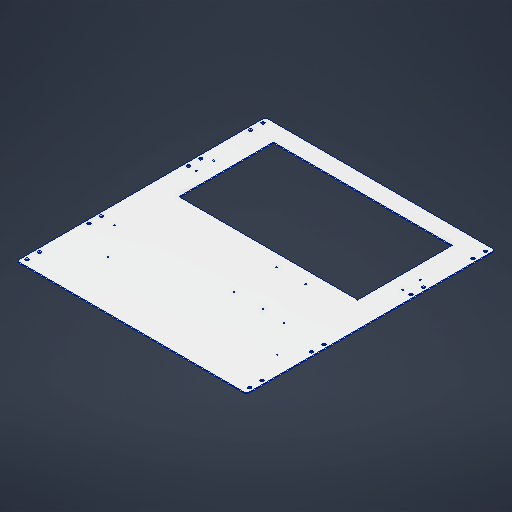
# Autodesk Inventor part: Base Plate
Saved by Autodesk Inventor 2026.2 (Build 302298010, 298A)
## iProperties
Created: 2026-03-19
Part Number: Base Plate
Material: Aluminum 6061
Document SubType Name: Sheet Metal
Designer: User
Density: 2.7 g/cm^3
Sheet Metal Rule: Default_mm
Appearance: Aluminum - Flat
Author: User
Autodesk Inventor part; units mm, degrees
ref_plane "YZ Plane" through (0, 0, 0) normal (1, 0, 0) x (0, 1, 0)
ref_plane "XZ Plane" through (0, 0, 0) normal (0, 1, 0) x (-1, 0, 0)
ref_plane "XY Plane" through (0, 0, 0) normal (0, 0, 1) x (1, 0, 0)
sketch "Sketch1" plane through (0, 0, 0) normal (0, 1, 0) x (-1, 0, 0)
  line L0 (-231.25, -250) -> (231.25, -250)
  line L1 (231.25, -250) -> (231.25, 250)
  line L2 (231.25, 250) -> (-231.25, 250)
  line L3 (-231.25, 250) -> (-231.25, -250)
  line L4 (-231.25, -250) -> (231.25, 250) construction
  line L5 (231.25, -250) -> (-231.25, 250) construction
  point P0 (0, 0)
  point P1 (0, 0)
  constraints: 12 end point, 2 midpoint, 2 parallel, 1 coincident, 1 horizontal, 1 perpendicular
extrude "Plate1" add sketch "Sketch1" along normal blind 2
sketch "Sketch5" plane through (0, 2, 0) normal (0, 1, 0) x (1, 0, 0)
  line L0 (-231.25, -250) -> (231.25, -250) projected
  line L1 (231.25, -250) -> (215, -250)
  line L2 (-231.25, 250) -> (-231.25, -250) projected
  line L3 (231.25, -250) -> (231.25, 250) projected
  line L4 (231.25, -225) -> (238.202, -225) construction
  line L5 (223.932, -237) -> (223.932, -250)
  line L6 (223.932, -237) -> (223.932, -212)
  line L7 (223.932, -212) -> (223.932, -187)
  line L8 (223.932, -187) -> (223.932, -162)
  line L9 (223.932, -237) -> (231.25, -237)
  line L10 (223.932, -162) -> (223.932, -137)
  line L11 (223.932, -137) -> (223.932, -112)
  line L12 (223.932, -112) -> (223.932, -87)
  line L13 (223.932, -87) -> (223.932, -62)
  line L14 (223.932, -62) -> (223.932, -37)
  line L15 (223.932, 13) -> (223.932, 38)
  line L16 (223.932, 38) -> (223.932, 63)
  line L17 (223.932, 63) -> (223.932, 88)
  line L18 (223.932, 88) -> (223.932, 113)
  line L19 (223.932, 113) -> (223.932, 138)
  line L20 (223.932, 138) -> (223.932, 163)
  line L21 (223.932, 163) -> (223.932, 188)
  line L22 (223.932, 188) -> (223.932, 213)
  line L23 (223.932, 213) -> (223.932, 238)
  line L24 (223.932, 238) -> (223.932, 250)
  line L25 (231.25, 250) -> (-231.25, 250) projected
  line L26 (223.932, -37) -> (223.932, -12)
  line L27 (223.932, -12) -> (223.932, 13)
  line L28 (-231.25, -250) -> (-223.932, -250)
  line L29 (-223.932, -250) -> (-223.932, -237)
  line L30 (-223.932, -237) -> (-223.932, -212)
  line L31 (-223.932, -212) -> (-223.932, -112)
  line L32 (-223.932, -112) -> (-223.932, -87)
  line L33 (-223.932, -87) -> (-223.932, 88)
  line L34 (-223.932, 88) -> (-223.932, 113)
  line L35 (-223.932, 113) -> (-223.932, 213)
  line L36 (-223.932, 213) -> (-223.932, 238)
  line L37 (-223.932, 238) -> (-223.932, 250)
  point P0 (0, 0)
  dimension "d126" = 13
  dimension "d127" = 25
  dimension "d128" = 25
  dimension "d129" = 25
  dimension "d130" = 7.318
  dimension "d131" = 25
  dimension "d132" = 25
  dimension "d133" = 25
  dimension "d134" = 25
  dimension "d135" = 25
  dimension "d138" = 25
  dimension "d139" = 25
  dimension "d140" = 25
  dimension "d141" = 25
  dimension "d142" = 25
  dimension "d143" = 25
  dimension "d144" = 25
  dimension "d145" = 25
  dimension "d146" = 25
  dimension "d147" = 25
  dimension "d148" = 7.318
  dimension "d149" = 13
  dimension "d150" = 25
  dimension "d151" = 100
  dimension "d152" = 25
  dimension "d153" = 175
  dimension "d154" = 25
  dimension "d155" = 100
  dimension "d156" = 25
  constraints: 68 end point, 28 point on line, 16 coincident, 5 vertical, 3 perpendicular, 1 collinear, 1 horizontal
  measures "d126" distance of L5.start L5.end
  measures "d127" distance of L5.start L6.end
  measures "d128" distance of L6.end L7.end
  measures "d129" distance of L7.end L8.end
  measures "d130" distance of L5.start L9.end
  measures "d131" distance of L8.end L10.end
  measures "d132" distance of L10.end L11.end
  measures "d133" distance of L11.end L12.end
  measures "d134" distance of L12.end L13.end
  measures "d135" distance of L13.end L14.end
  measures "d138" distance of L15.start L15.end
  measures "d139" distance of L15.end L16.end
  measures "d140" distance of L16.end L17.end
  measures "d141" distance of L17.end L18.end
  measures "d142" distance of L18.end L19.end
  measures "d143" distance of L19.end L20.end
  measures "d144" distance of L20.end L21.end
  measures "d145" distance of L21.end L22.end
  measures "d146" distance of L22.end L23.end
  measures "d147" distance of L14.end L26.end
  measures "d148" distance of L0.start L28.end
  measures "d149" distance of L28.end L29.end
  measures "d150" distance of L29.end L30.end
  measures "d151" distance of L31.start L31.end
  measures "d152" distance of L31.end L32.end
  measures "d153" distance of L33.start L33.end
  measures "d154" distance of L33.end L34.end
  measures "d155" distance of L34.end L35.end
  measures "d156" distance of L35.end L36.end
hole "Hole1" at (223.932, 2, 237) at (223.932, 2, 212) at (223.932, 2, 112) at (223.932, 2, 87) at (223.932, 2, -113) at (223.932, 2, -88) at (223.932, 2, -238) at (223.932, 2, -213) at (-223.932, 2, 237) at (-223.932, 2, 212) at (-223.932, 2, 112) at (-223.932, 2, 87) at (-223.932, 2, -88) at (-223.932, 2, -113) at (-223.932, 2, -213) at (-223.932, 2, -238) direction (0, -1, 0) diameter 6.5 end through all
fillet "Corner Round1" radius 5 4 edges at (231.25, 1, -250) (231.25, 1, 250) (-231.25, 1, -250) (-231.25, 1, 250)
sketch "Sketch6" plane through (0, 2, 0) normal (0, 1, 0) x (1, 0, 0)
  line L0 (0, 250) -> (-62.5, 250)
  line L1 (62.5, 250) -> (62.5, 215)
  line L2 (-231.25, -245) -> (-231.25, 245) projected
  line L3 (231.25, 245) -> (231.25, -245) projected
  line L4 (0, 215) -> (180, 215)
  line L5 (0, 215) -> (-180, 215)
  line L6 (-180, 215) -> (-180, 25)
  line L7 (-180, 25) -> (180, 25)
  line L8 (180, 25) -> (180, 215)
  point P0 (0, 0)
  point P1 (-50, 250)
  dimension "d116" = 35
  dimension "d122" = 180
  dimension "d123" = 180
  dimension "d124" = 190
  dimension "d125" = 360
  constraints: 14 end point, 3 perpendicular, 1 horizontal
  measures "d116" distance of L1.start L1.end
  measures "d122" distance of L4.start L4.end
  measures "d123" distance of L4.start L5.end
  measures "d124" distance of L5.end L6.end
  measures "d125" distance of L6.end L7.end
extrude "Cut1" cut sketch "Sketch6" against normal blind 2
sketch "Sketch7" plane through (0, 2, 0) normal (0, 1, 0) x (1, 0, 0)
  line L0 (-226.25, -250) -> (226.25, -250) projected
  line L1 (-225.002, -250) -> (-195.002, -250)
  line L2 (-195.002, -250) -> (-195.002, -152)
  line L3 (-195.002, -152) -> (-146.002, -152)
  line L4 (-146.002, -152) -> (-146.002, -90)
  line L5 (-146.002, -90) -> (-195.002, -90)
  line L6 (225, -250) -> (195, -250)
  line L7 (195, -250) -> (195, -152)
  line L8 (195, -152) -> (146, -152)
  line L9 (146, -152) -> (146, -90)
  line L10 (146, -90) -> (195, -90)
  point P0 (0, 0)
  dimension "d83" = 30
  dimension "d84" = 98
  dimension "d85" = 49
  dimension "d86" = 62
  dimension "d87" = 30
  dimension "d88" = 98
  dimension "d89" = 49
  dimension "d90" = 62
  dimension "d173" = 49
  constraints: 20 end point, 7 perpendicular, 4 coincident, 3 point on line, 1 vertical
  measures "d83" distance of L1.start L1.end
  measures "d84" distance of L1.end L2.end
  measures "d85" distance of L2.end L3.end
  measures "d86" distance of L4.start L4.end
  measures "d87" distance of L6.start L6.end
  measures "d88" distance of L6.end L7.end
  measures "d89" distance of L7.end L8.end
  measures "d90" distance of L8.end L9.end
  measures "d173" distance of L4.end L5.end
hole "Hole2" at (-146.002, 2, 152) at (-195.002, 2, 90) at (195, 2, 152) at (146, 2, 90) direction (0, -1, 0) diameter 2.2 end through all
sketch "Sketch9" plane through (0, 2, 0) normal (0, 1, 0) x (1, 0, 0)
  line L0 (-226.25, 250) -> (226.25, 250) projected
  line L1 (-114.2161, 250) -> (35.7839, 250) construction
  line L2 (0, 0) -> (100, 0)
  line L3 (100, 0) -> (100, -86)
  line L4 (100, -86) -> (42, -86)
  line L5 (42, -86) -> (42, 0)
  point P0 (-55, 250)
  point P1 (-62.5, 250)
  dimension "d103" = 100
  dimension "d104" = 86
  dimension "d105" = 58
  constraints: 10 end point, 4 coincident, 3 perpendicular, 2 horizontal, 2 point on line
  measures "d103" distance of L2.start L2.end
  measures "d104" distance of L2.end L3.end
  measures "d105" distance of L3.end L4.end
hole "Hole4" at (42, 2, 0) at (100, 2, 0) at (100, 2, 86) at (42, 2, 86) direction (0, -1, 0) diameter 2.75 end through all
sketch "Sketch11" plane through (0, 2, 0) normal (0, 1, 0) x (1, 0, 0)
  line L0 (-180, 25) -> (180, 25) projected
  line L1 (180, 25) -> (180, 105)
  line L2 (180, 215) -> (180, 25) projected
  line L3 (180, 105) -> (207.75, 105)
  line L4 (207.75, 105) -> (207.75, 87.5)
  line L5 (207.75, 105) -> (207.75, 123)
  point P0 (0, 0)
  dimension "d159" = 80
  dimension "d160" = 27.75
  dimension "d161" = 17.5
  dimension "d162" = 18
  constraints: 8 end point, 2 coincident, 2 vertical, 1 perpendicular, 1 point on line
  measures "d159" distance of L0.end L1.end
  measures "d160" distance of L1.end L3.end
  measures "d161" distance of L3.end L4.end
  measures "d162" distance of L3.end L5.end
hole "Hole5" at (207.75, 2, -87.5) at (207.75, 2, -123) direction (0, -1, 0) diameter 3.2 end through all
pattern_linear "Rectangular Pattern1" count 2 spacing 415.5 along (-1, 0, 0) of "Hole5"
equation "\"d54\" = Thickness"
equation "\"d65\" = Thickness"
equation "\"d81\" = Thickness"
equation "\"d168\" = Thickness"
equation "\"d2\" = Thickness"
equation "\"BendRadius\" = Thickness"
equation "\"BendReliefWidth\" = Thickness"
equation "\"BendReliefDepth\" = 0.5 * Thickness"
equation "\"CornerReliefSize\" = 4 * Thickness"
equation "\"MinimumRemnant\" = 2 * Thickness"
equation "\"TransitionRadius\" = BendRadius"
equation "\"JacobiRadiusSize\" = BendRadius"
equation "\"GapSize\" = Thickness"
equation "\"Thickness\" = 2"
body "Solid1"
